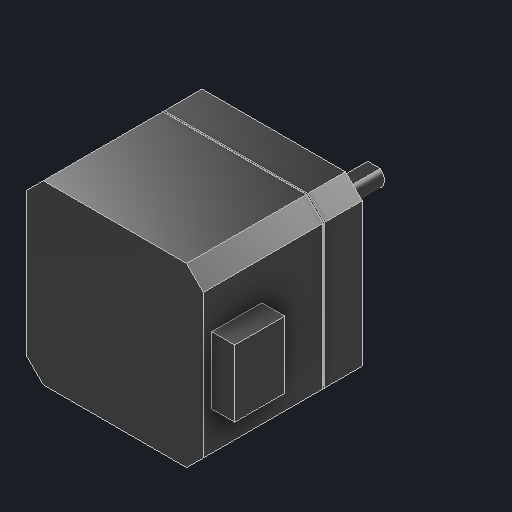
# Autodesk Inventor part: nema17_42x38
Saved by Autodesk Inventor 2027.1 (Build 311270010, 270A)
## iProperties
Created: 2026-11-04
Part Number: nema17_42x38
Material: Generic
Description: NEMA 17 42x38 mm stepper, 1.8 deg, 1.5 A / 3.8 V, 5 mm D-shaft 24 mm, M3 on 31 mm (SIMAX3D)
Document SubType Name: Modeling
Designer: Claude (from photos)
Density: 1 g/cm^3
Appearance: Glossy - Black
Author: alexg
Autodesk Inventor part; units mm, degrees
sketch "Body 42.3 x 42.3 x 38 sketch" plane through (0, 0, 0) normal (0, 0, 1) x (1, 0, 0)
  line L0 (-17.15, -21.15) -> (17.15, -21.15)
  line L1 (17.15, -21.15) -> (21.15, -17.15)
  line L2 (21.15, -17.15) -> (21.15, 17.15)
  line L3 (21.15, 17.15) -> (17.15, 21.15)
  line L4 (17.15, 21.15) -> (-17.15, 21.15)
  line L5 (-17.15, 21.15) -> (-21.15, 17.15)
  line L6 (-21.15, 17.15) -> (-21.15, -17.15)
  line L7 (-21.15, -17.15) -> (-17.15, -21.15)
  constraints: 16 end point
extrude "Body 42.3 x 42.3 x 38" add sketch "Body 42.3 x 42.3 x 38 sketch" along normal blind 38
sketch "M3 holes 4.5 deep sketch" plane through (0, 0, 0) normal (0, 0, 1) x (1, 0, 0)
  circle A0 centre (-15.5, -15.5) radius 1.5
  circle A1 centre (-15.5, 15.5) radius 1.5
  circle A2 centre (15.5, -15.5) radius 1.5
  circle A3 centre (15.5, 15.5) radius 1.5
  constraints: 4 centre point
extrude "M3 holes 4.5 deep" cut sketch "M3 holes 4.5 deep sketch" along normal blind 4.5
sketch "Pilot boss 22 x 2 sketch" plane through (0, 0, 0) normal (0, 0, 1) x (1, 0, 0)
  circle A0 centre (0, 0) radius 11
  constraints: 1 centre point
extrude "Pilot boss 22 x 2" add sketch "Pilot boss 22 x 2 sketch" against normal blind 2
ref_plane "Work Plane1" through (0, 0, -2) normal (0, 0, 1) x (1, 0, 0)
sketch "Shaft 5 x 24 sketch" plane through (0, 0, -2) normal (0, 0, 1) x (1, 0, 0)
  circle A0 centre (0, 0) radius 2.5
  constraints: 1 centre point
extrude "Shaft 5 x 24" add sketch "Shaft 5 x 24 sketch" against normal blind 22
ref_plane "Work Plane2" through (0, 2, 0) normal (0, 1, 0) x (-1, 0, 0)
sketch "Shaft D-flat (4.5) sketch" plane through (0, 2, 0) normal (0, 1, 0) x (-1, 0, 0)
  line L0 (3, -24) -> (-3, -24)
  line L1 (-3, -24) -> (-3, -9)
  line L2 (-3, -9) -> (3, -9)
  line L3 (3, -9) -> (3, -24)
  constraints: 8 end point, 2 parallel, 1 horizontal, 1 perpendicular
extrude "Shaft D-flat (4.5)" cut sketch "Shaft D-flat (4.5) sketch" along normal blind 1
ref_plane "Work Plane3" through (21.15, 0, 0) normal (1, 0, 0) x (0, 1, 0)
sketch "Connector 6-pin (cable detachable) sketch" plane through (21.15, 0, 0) normal (1, 0, 0) x (0, 1, 0)
  line L0 (-8, 24) -> (8, 24)
  line L1 (8, 24) -> (8, 36)
  line L2 (8, 36) -> (-8, 36)
  line L3 (-8, 36) -> (-8, 24)
  constraints: 8 end point, 2 parallel, 1 horizontal, 1 perpendicular
extrude "Connector 6-pin (cable detachable)" add sketch "Connector 6-pin (cable detachable) sketch" along normal blind 5.5
ref_plane "Work Plane4" through (0, 0, 9) normal (0, 0, 1) x (1, 0, 0)
sketch "Stator groove sketch" plane through (0, 0, 9) normal (0, 0, 1) x (1, 0, 0)
  line L0 (-17.35, -21.35) -> (17.35, -21.35)
  line L1 (17.35, -21.35) -> (21.35, -17.35)
  line L2 (21.35, -17.35) -> (21.35, 17.35)
  line L3 (21.35, 17.35) -> (17.35, 21.35)
  line L4 (17.35, 21.35) -> (-17.35, 21.35)
  line L5 (-17.35, 21.35) -> (-21.35, 17.35)
  line L6 (-21.35, 17.35) -> (-21.35, -17.35)
  line L7 (-21.35, -17.35) -> (-17.35, -21.35)
  line L8 (-16.85, -20.85) -> (16.85, -20.85)
  line L9 (16.85, -20.85) -> (20.85, -16.85)
  line L10 (20.85, -16.85) -> (20.85, 16.85)
  line L11 (20.85, 16.85) -> (16.85, 20.85)
  line L12 (16.85, 20.85) -> (-16.85, 20.85)
  line L13 (-16.85, 20.85) -> (-20.85, 16.85)
  line L14 (-20.85, 16.85) -> (-20.85, -16.85)
  line L15 (-20.85, -16.85) -> (-16.85, -20.85)
  constraints: 32 end point
extrude "Stator groove" cut sketch "Stator groove sketch" along normal blind 0.4
body "Solid1"
